Autodesk Fusion 360 part; units mm, degrees
(part 7 of 7)
equation "d891 = tubeRimChamfer"
equation "d894 = bodyWidth / 2"
equation "d896 = abs(( 1 ) * ( ( -1 ) * cordStation ) + ( 0 ) * ( 0 mm ))"
equation "d898 = -( wall )"
equation "d900 = bedRelief"
equation "d903 = bodyWidth / 2"
equation "d905 = abs(( -1 ) * ( ( -1 ) * cordStation ) + ( 0 ) * ( 0 mm ))"
equation "d907 = -( wall )"
equation "d909 = bedRelief"
named bodies: "A Housing print", "B Moving Body print"
